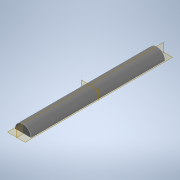
# Autodesk Inventor part: Staffa
Saved by Autodesk Inventor 2021 (Build 250183000, 183)
## iProperties
Created: 2026-04-24
Part Number: Staffa
Material: Generic
Document SubType Name: Modeling
Designer: Admin
Density: 1 g/cm^3
Appearance: Gray
Author: Admin
Autodesk Inventor part; units mm, degrees
sketch "Sketch1" plane through (0, 0, 0) normal (0, 0, 1) x (1, 0, 0)
  circle A0 centre (0, 0) radius 4.4
  line L0 (-4.4, 0) -> (4.4, 0)
  line L1 (-6.16, 0) -> (6.16, 0) projected
  dimension "d0" = 8.8
  constraints: 2 end point, 2 midpoint, 2 point on circle, 1 centre point, 1 coincident, 1 horizontal
  measures "d0" diameter of A0
extrude "Extrusion1" add sketch "Sketch1" along normal mid plane 73 contours L0 A0 picked at (-0.9585, 2.2396)
body "Solid1"
